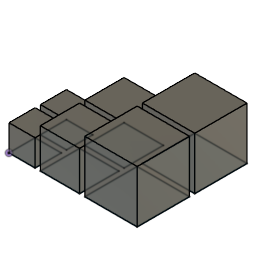
Test Cubes (Autodesk Fusion 360 design; units mm, degrees)
Autodesk Fusion 360 part; units mm, degrees
sketch "Sketch1" plane through (0, 0, 0) normal (0, 0, 1) x (1, 0, 0)
  line L0 (0, 0) -> (12.7, 0)
  line L1 (12.7, 0) -> (12.7, 12.7)
  line L2 (12.7, 12.7) -> (0, 12.7)
  line L3 (0, 12.7) -> (0, 0)
  line L4 (15.24, 0) -> (34.29, 0)
  line L5 (34.29, 0) -> (34.29, 19.05)
  line L6 (34.29, 19.05) -> (15.24, 19.05)
  line L7 (15.24, 19.05) -> (15.24, 0)
  line L8 (36.83, 0) -> (62.23, 0)
  line L9 (62.23, 0) -> (62.23, 25.4)
  line L10 (62.23, 25.4) -> (36.83, 25.4)
  line L11 (36.83, 25.4) -> (36.83, 0)
  line L12 (0, 15.24) -> (12.7, 15.24)
  line L13 (12.7, 15.24) -> (12.7, 27.94)
  line L14 (12.7, 27.94) -> (0, 27.94)
  line L15 (0, 27.94) -> (0, 15.24)
  line L16 (15.24, 21.59) -> (34.29, 21.59)
  line L17 (34.29, 21.59) -> (34.29, 40.64)
  line L18 (34.29, 40.64) -> (15.24, 40.64)
  line L19 (15.24, 40.64) -> (15.24, 21.59)
  line L20 (36.83, 27.94) -> (62.23, 27.94)
  line L21 (62.23, 27.94) -> (62.23, 53.34)
  line L22 (62.23, 53.34) -> (36.83, 53.34)
  line L23 (36.83, 53.34) -> (36.83, 27.94)
  dimension "d1" = 12.7
  dimension "d2" = 12.7
  dimension "d3" = 19.05
  dimension "d4" = 19.05
  dimension "d5" = 25.4
  dimension "d6" = 25.4
  dimension "d7" = 25.4
  dimension "d8" = 25.4
  dimension "d9" = 19.05
  dimension "d10" = 19.05
  dimension "d11" = 12.7
  dimension "d12" = 12.7
  dimension "d13" = 2.54
  dimension "d14" = 2.54
  dimension "d15" = 2.54
  dimension "d16" = 2.54
  dimension "d17" = 2.54
  constraint horizontal L0
  constraint vertical L1
  constraint horizontal L2
  constraint vertical L3
  constraint coincident L0.start L3.end
  constraint horizontal L4
  constraint vertical L5
  constraint horizontal L6
  constraint vertical L7
  constraint horizontal L8
  constraint vertical L9
  constraint horizontal L10
  constraint vertical L11
  constraint horizontal L12
  constraint vertical L13
  constraint horizontal L14
  constraint vertical L15
  constraint horizontal L16
  constraint vertical L17
  constraint horizontal L18
  constraint vertical L19
  constraint horizontal L20
  constraint vertical L21
  constraint horizontal L22
  constraint vertical L23
  constraint vertical L2.end L12.start
  constraint horizontal L0.end L4.start
  constraint horizontal L4.start L8.start
  constraint vertical L6.end L16.start
  constraint vertical L10.end L20.start
  measures "d1" distance of L0.start L0.end
  measures "d2" distance of L0.start L2.end
  measures "d3" distance of L4.start L4.end
  measures "d4" distance of L4.start L6.end
  measures "d5" distance of L8.start L8.end
  measures "d6" distance of L8.start L10.end
  measures "d7" distance of L20.start L20.end
  measures "d8" distance of L20.start L22.end
  measures "d9" distance of L16.start L16.end
  measures "d10" distance of L16.start L18.end
  measures "d11" distance of L12.start L12.end
  measures "d12" distance of L12.start L14.end
  measures "d13" distance of L2 L12
  measures "d14" distance of L6 L16
  measures "d15" distance of L10 L20
  measures "d16" distance of L1 L7
  measures "d17" distance of L5 L11
extrude "Extrude1" add sketch "Sketch1" along normal blind 12.7 contours L0 L1 L2 L3 | L12 L13 L14 L15 makes body 1 at (8.4667, 27.94, 8.4667) makes body 2 at (0, 8.4667, 4.2333)
extrude "Extrude2" add sketch "Sketch1" along normal blind 19.05 separate body contours L4 L5 L6 L7 | L16 L17 L18 L19 makes body 3 at (21.59, 12.7, 0) makes body 4 at (21.59, 40.64, 6.35)
extrude "Extrude3" add sketch "Sketch1" along normal blind 25.4 separate body contours L8 L9 L10 L11 | L20 L21 L22 L23 makes body 5 at (36.83, 44.8733, 8.4667) makes body 6 at (36.83, 16.9333, 8.4667)
